Autodesk Fusion 360 part; units mm, degrees
(part 2 of 2)
  circle A756 centre (-67.5, 10.9286) radius 0.5
  circle A757 centre (-64.2073, 10.9286) radius 0.5
  circle A758 centre (-60.9146, 10.9286) radius 0.5
  circle A759 centre (-57.622, 10.9286) radius 0.5
  circle A760 centre (-54.3293, 10.9286) radius 0.5
  circle A761 centre (-51.0366, 10.9286) radius 0.5
  circle A762 centre (-47.7439, 10.9286) radius 0.5
  circle A763 centre (-44.4512, 10.9286) radius 0.5
  circle A764 centre (-41.1585, 10.9286) radius 0.5
  circle A765 centre (-37.8659, 10.9286) radius 0.5
  circle A766 centre (-34.5732, 10.9286) radius 0.5
  circle A767 centre (-31.2805, 10.9286) radius 0.5
  circle A768 centre (-27.9878, 10.9286) radius 0.5
  circle A769 centre (-24.6951, 10.9286) radius 0.5
  circle A770 centre (-21.4024, 10.9286) radius 0.5
  circle A771 centre (-18.1098, 10.9286) radius 0.5
  circle A772 centre (-14.8171, 10.9286) radius 0.5
  circle A773 centre (-11.5244, 10.9286) radius 0.5
  circle A774 centre (-8.2317, 10.9286) radius 0.5
  circle A775 centre (-4.939, 10.9286) radius 0.5
  circle A776 centre (-1.6463, 10.9286) radius 0.5
  circle A777 centre (1.6463, 10.9286) radius 0.5
  circle A778 centre (4.939, 10.9286) radius 0.5
  circle A779 centre (8.2317, 10.9286) radius 0.5
  circle A780 centre (11.5244, 10.9286) radius 0.5
  circle A781 centre (14.8171, 10.9286) radius 0.5
  circle A782 centre (18.1098, 10.9286) radius 0.5
  circle A783 centre (21.4024, 10.9286) radius 0.5
  circle A784 centre (24.6951, 10.9286) radius 0.5
  circle A785 centre (27.9878, 10.9286) radius 0.5
  circle A786 centre (31.2805, 10.9286) radius 0.5
  circle A787 centre (34.5732, 10.9286) radius 0.5
  circle A788 centre (37.8659, 10.9286) radius 0.5
  circle A789 centre (41.1585, 10.9286) radius 0.5
  circle A790 centre (44.4512, 10.9286) radius 0.5
  circle A791 centre (47.7439, 10.9286) radius 0.5
  circle A792 centre (51.0366, 10.9286) radius 0.5
  circle A793 centre (54.3293, 10.9286) radius 0.5
  circle A794 centre (57.622, 10.9286) radius 0.5
  circle A795 centre (60.9146, 10.9286) radius 0.5
  circle A796 centre (64.2073, 10.9286) radius 0.5
  circle A797 centre (67.5, 10.9286) radius 0.5
  circle A798 centre (-67.5, 13.7857) radius 0.5
  circle A799 centre (-64.2073, 13.7857) radius 0.5
  circle A800 centre (-60.9146, 13.7857) radius 0.5
  circle A801 centre (-57.622, 13.7857) radius 0.5
  circle A802 centre (-54.3293, 13.7857) radius 0.5
  circle A803 centre (-51.0366, 13.7857) radius 0.5
  circle A804 centre (-47.7439, 13.7857) radius 0.5
  circle A805 centre (-44.4512, 13.7857) radius 0.5
  circle A806 centre (-41.1585, 13.7857) radius 0.5
  circle A807 centre (-37.8659, 13.7857) radius 0.5
  circle A808 centre (-34.5732, 13.7857) radius 0.5
  circle A809 centre (-31.2805, 13.7857) radius 0.5
  circle A810 centre (-27.9878, 13.7857) radius 0.5
  circle A811 centre (-24.6951, 13.7857) radius 0.5
  circle A812 centre (-21.4024, 13.7857) radius 0.5
  circle A813 centre (-18.1098, 13.7857) radius 0.5
  circle A814 centre (-14.8171, 13.7857) radius 0.5
  circle A815 centre (-11.5244, 13.7857) radius 0.5
  circle A816 centre (-8.2317, 13.7857) radius 0.5
  circle A817 centre (-4.939, 13.7857) radius 0.5
  circle A818 centre (-1.6463, 13.7857) radius 0.5
  circle A819 centre (1.6463, 13.7857) radius 0.5
  circle A820 centre (4.939, 13.7857) radius 0.5
  circle A821 centre (8.2317, 13.7857) radius 0.5
  circle A822 centre (11.5244, 13.7857) radius 0.5
  circle A823 centre (14.8171, 13.7857) radius 0.5
  circle A824 centre (18.1098, 13.7857) radius 0.5
  circle A825 centre (21.4024, 13.7857) radius 0.5
  circle A826 centre (24.6951, 13.7857) radius 0.5
  circle A827 centre (27.9878, 13.7857) radius 0.5
  circle A828 centre (31.2805, 13.7857) radius 0.5
  circle A829 centre (34.5732, 13.7857) radius 0.5
  circle A830 centre (37.8659, 13.7857) radius 0.5
  circle A831 centre (41.1585, 13.7857) radius 0.5
  circle A832 centre (44.4512, 13.7857) radius 0.5
  circle A833 centre (47.7439, 13.7857) radius 0.5
  circle A834 centre (51.0366, 13.7857) radius 0.5
  circle A835 centre (54.3293, 13.7857) radius 0.5
  circle A836 centre (57.622, 13.7857) radius 0.5
  circle A837 centre (60.9146, 13.7857) radius 0.5
  circle A838 centre (64.2073, 13.7857) radius 0.5
  circle A839 centre (67.5, 13.7857) radius 0.5
  circle A840 centre (-67.5, 16.6429) radius 0.5
  circle A841 centre (-64.2073, 16.6429) radius 0.5
  circle A842 centre (-60.9146, 16.6429) radius 0.5
  circle A843 centre (-57.622, 16.6429) radius 0.5
  circle A844 centre (-54.3293, 16.6429) radius 0.5
  circle A845 centre (-51.0366, 16.6429) radius 0.5
  circle A846 centre (-47.7439, 16.6429) radius 0.5
  circle A847 centre (-44.4512, 16.6429) radius 0.5
  circle A848 centre (-41.1585, 16.6429) radius 0.5
  circle A849 centre (-37.8659, 16.6429) radius 0.5
  circle A850 centre (-34.5732, 16.6429) radius 0.5
  circle A851 centre (-31.2805, 16.6429) radius 0.5
  circle A852 centre (-27.9878, 16.6429) radius 0.5
  circle A853 centre (-24.6951, 16.6429) radius 0.5
  circle A854 centre (-21.4024, 16.6429) radius 0.5
  circle A855 centre (-18.1098, 16.6429) radius 0.5
  circle A856 centre (-14.8171, 16.6429) radius 0.5
  circle A857 centre (-11.5244, 16.6429) radius 0.5
  circle A858 centre (-8.2317, 16.6429) radius 0.5
  circle A859 centre (-4.939, 16.6429) radius 0.5
  circle A860 centre (-1.6463, 16.6429) radius 0.5
  circle A861 centre (1.6463, 16.6429) radius 0.5
  circle A862 centre (4.939, 16.6429) radius 0.5
  circle A863 centre (8.2317, 16.6429) radius 0.5
  circle A864 centre (11.5244, 16.6429) radius 0.5
  circle A865 centre (14.8171, 16.6429) radius 0.5
  circle A866 centre (18.1098, 16.6429) radius 0.5
  circle A867 centre (21.4024, 16.6429) radius 0.5
  circle A868 centre (24.6951, 16.6429) radius 0.5
  circle A869 centre (27.9878, 16.6429) radius 0.5
  circle A870 centre (31.2805, 16.6429) radius 0.5
  circle A871 centre (34.5732, 16.6429) radius 0.5
  circle A872 centre (37.8659, 16.6429) radius 0.5
  circle A873 centre (41.1585, 16.6429) radius 0.5
  circle A874 centre (44.4512, 16.6429) radius 0.5
  circle A875 centre (47.7439, 16.6429) radius 0.5
  circle A876 centre (51.0366, 16.6429) radius 0.5
  circle A877 centre (54.3293, 16.6429) radius 0.5
  circle A878 centre (57.622, 16.6429) radius 0.5
  circle A879 centre (60.9146, 16.6429) radius 0.5
  circle A880 centre (64.2073, 16.6429) radius 0.5
  circle A881 centre (67.5, 16.6429) radius 0.5
  circle A882 centre (-67.5, 19.5) radius 0.5
  circle A883 centre (-64.2073, 19.5) radius 0.5
  circle A884 centre (-60.9146, 19.5) radius 0.5
  circle A885 centre (-57.622, 19.5) radius 0.5
  circle A886 centre (-54.3293, 19.5) radius 0.5
  circle A887 centre (-51.0366, 19.5) radius 0.5
  circle A888 centre (-47.7439, 19.5) radius 0.5
  circle A889 centre (-44.4512, 19.5) radius 0.5
  circle A890 centre (-41.1585, 19.5) radius 0.5
  circle A891 centre (-37.8659, 19.5) radius 0.5
  circle A892 centre (-34.5732, 19.5) radius 0.5
  circle A893 centre (-31.2805, 19.5) radius 0.5
  circle A894 centre (-27.9878, 19.5) radius 0.5
  circle A895 centre (-24.6951, 19.5) radius 0.5
  circle A896 centre (-21.4024, 19.5) radius 0.5
  circle A897 centre (-18.1098, 19.5) radius 0.5
  circle A898 centre (-14.8171, 19.5) radius 0.5
  circle A899 centre (-11.5244, 19.5) radius 0.5
  circle A900 centre (-8.2317, 19.5) radius 0.5
  circle A901 centre (-4.939, 19.5) radius 0.5
  circle A902 centre (-1.6463, 19.5) radius 0.5
  circle A903 centre (1.6463, 19.5) radius 0.5
  circle A904 centre (4.939, 19.5) radius 0.5
  circle A905 centre (8.2317, 19.5) radius 0.5
  circle A906 centre (11.5244, 19.5) radius 0.5
  circle A907 centre (14.8171, 19.5) radius 0.5
  circle A908 centre (18.1098, 19.5) radius 0.5
  circle A909 centre (21.4024, 19.5) radius 0.5
  circle A910 centre (24.6951, 19.5) radius 0.5
  circle A911 centre (27.9878, 19.5) radius 0.5
  circle A912 centre (31.2805, 19.5) radius 0.5
  circle A913 centre (34.5732, 19.5) radius 0.5
  circle A914 centre (37.8659, 19.5) radius 0.5
  circle A915 centre (41.1585, 19.5) radius 0.5
  circle A916 centre (44.4512, 19.5) radius 0.5
  circle A917 centre (47.7439, 19.5) radius 0.5
  circle A918 centre (51.0366, 19.5) radius 0.5
  circle A919 centre (54.3293, 19.5) radius 0.5
  circle A920 centre (57.622, 19.5) radius 0.5
  circle A921 centre (60.9146, 19.5) radius 0.5
  circle A922 centre (64.2073, 19.5) radius 0.5
  circle A923 centre (67.5, 19.5) radius 0.5
  circle A924 centre (-67.5, 22.3571) radius 0.5
  circle A925 centre (-64.2073, 22.3571) radius 0.5
  circle A926 centre (-60.9146, 22.3571) radius 0.5
  circle A927 centre (-57.622, 22.3571) radius 0.5
  circle A928 centre (-54.3293, 22.3571) radius 0.5
  circle A929 centre (-51.0366, 22.3571) radius 0.5
  circle A930 centre (-47.7439, 22.3571) radius 0.5
  circle A931 centre (-44.4512, 22.3571) radius 0.5
  circle A932 centre (-41.1585, 22.3571) radius 0.5
  circle A933 centre (-37.8659, 22.3571) radius 0.5
  circle A934 centre (-34.5732, 22.3571) radius 0.5
  circle A935 centre (-31.2805, 22.3571) radius 0.5
  circle A936 centre (-27.9878, 22.3571) radius 0.5
  circle A937 centre (-24.6951, 22.3571) radius 0.5
  circle A938 centre (-21.4024, 22.3571) radius 0.5
  circle A939 centre (-18.1098, 22.3571) radius 0.5
  circle A940 centre (-14.8171, 22.3571) radius 0.5
  circle A941 centre (-11.5244, 22.3571) radius 0.5
  circle A942 centre (-8.2317, 22.3571) radius 0.5
  circle A943 centre (-4.939, 22.3571) radius 0.5
  circle A944 centre (-1.6463, 22.3571) radius 0.5
  circle A945 centre (1.6463, 22.3571) radius 0.5
  circle A946 centre (4.939, 22.3571) radius 0.5
  circle A947 centre (8.2317, 22.3571) radius 0.5
  circle A948 centre (11.5244, 22.3571) radius 0.5
  circle A949 centre (14.8171, 22.3571) radius 0.5
  circle A950 centre (18.1098, 22.3571) radius 0.5
  circle A951 centre (21.4024, 22.3571) radius 0.5
  circle A952 centre (24.6951, 22.3571) radius 0.5
  circle A953 centre (27.9878, 22.3571) radius 0.5
  circle A954 centre (31.2805, 22.3571) radius 0.5
  circle A955 centre (34.5732, 22.3571) radius 0.5
  circle A956 centre (37.8659, 22.3571) radius 0.5
  circle A957 centre (41.1585, 22.3571) radius 0.5
  circle A958 centre (44.4512, 22.3571) radius 0.5
  circle A959 centre (47.7439, 22.3571) radius 0.5
  circle A960 centre (51.0366, 22.3571) radius 0.5
  circle A961 centre (54.3293, 22.3571) radius 0.5
  circle A962 centre (57.622, 22.3571) radius 0.5
  circle A963 centre (60.9146, 22.3571) radius 0.5
  circle A964 centre (64.2073, 22.3571) radius 0.5
  circle A965 centre (67.5, 22.3571) radius 0.5
  circle A966 centre (-67.5, 25.2143) radius 0.5
  circle A967 centre (-64.2073, 25.2143) radius 0.5
  circle A968 centre (-60.9146, 25.2143) radius 0.5
  circle A969 centre (-57.622, 25.2143) radius 0.5
  circle A970 centre (-54.3293, 25.2143) radius 0.5
  circle A971 centre (-51.0366, 25.2143) radius 0.5
  circle A972 centre (-47.7439, 25.2143) radius 0.5
  circle A973 centre (-44.4512, 25.2143) radius 0.5
  circle A974 centre (-41.1585, 25.2143) radius 0.5
  circle A975 centre (-37.8659, 25.2143) radius 0.5
  circle A976 centre (-34.5732, 25.2143) radius 0.5
  circle A977 centre (-31.2805, 25.2143) radius 0.5
  circle A978 centre (-27.9878, 25.2143) radius 0.5
  circle A979 centre (-24.6951, 25.2143) radius 0.5
  circle A980 centre (-21.4024, 25.2143) radius 0.5
  circle A981 centre (-18.1098, 25.2143) radius 0.5
  circle A982 centre (-14.8171, 25.2143) radius 0.5
  circle A983 centre (-11.5244, 25.2143) radius 0.5
  circle A984 centre (-8.2317, 25.2143) radius 0.5
  circle A985 centre (-4.939, 25.2143) radius 0.5
  circle A986 centre (-1.6463, 25.2143) radius 0.5
  circle A987 centre (1.6463, 25.2143) radius 0.5
  circle A988 centre (4.939, 25.2143) radius 0.5
  circle A989 centre (8.2317, 25.2143) radius 0.5
  circle A990 centre (11.5244, 25.2143) radius 0.5
  circle A991 centre (14.8171, 25.2143) radius 0.5
  circle A992 centre (18.1098, 25.2143) radius 0.5
  circle A993 centre (21.4024, 25.2143) radius 0.5
  circle A994 centre (24.6951, 25.2143) radius 0.5
  circle A995 centre (27.9878, 25.2143) radius 0.5
  circle A996 centre (31.2805, 25.2143) radius 0.5
  circle A997 centre (34.5732, 25.2143) radius 0.5
  circle A998 centre (37.8659, 25.2143) radius 0.5
  circle A999 centre (41.1585, 25.2143) radius 0.5
  circle A1000 centre (44.4512, 25.2143) radius 0.5
  circle A1001 centre (47.7439, 25.2143) radius 0.5
  circle A1002 centre (51.0366, 25.2143) radius 0.5
  circle A1003 centre (54.3293, 25.2143) radius 0.5
  circle A1004 centre (57.622, 25.2143) radius 0.5
  circle A1005 centre (60.9146, 25.2143) radius 0.5
  circle A1006 centre (64.2073, 25.2143) radius 0.5
  circle A1007 centre (67.5, 25.2143) radius 0.5
  circle A1008 centre (-67.5, 28.0714) radius 0.5
  circle A1009 centre (-64.2073, 28.0714) radius 0.5
  circle A1010 centre (-60.9146, 28.0714) radius 0.5
  circle A1011 centre (-57.622, 28.0714) radius 0.5
  circle A1012 centre (-54.3293, 28.0714) radius 0.5
  circle A1013 centre (-51.0366, 28.0714) radius 0.5
  circle A1014 centre (-47.7439, 28.0714) radius 0.5
  circle A1015 centre (-44.4512, 28.0714) radius 0.5
  circle A1016 centre (-41.1585, 28.0714) radius 0.5
  circle A1017 centre (-37.8659, 28.0714) radius 0.5
  circle A1018 centre (-34.5732, 28.0714) radius 0.5
  circle A1019 centre (-31.2805, 28.0714) radius 0.5
  circle A1020 centre (-27.9878, 28.0714) radius 0.5
  circle A1021 centre (-24.6951, 28.0714) radius 0.5
  circle A1022 centre (-21.4024, 28.0714) radius 0.5
  circle A1023 centre (-18.1098, 28.0714) radius 0.5
  circle A1024 centre (-14.8171, 28.0714) radius 0.5
  circle A1025 centre (-11.5244, 28.0714) radius 0.5
  circle A1026 centre (-8.2317, 28.0714) radius 0.5
  circle A1027 centre (-4.939, 28.0714) radius 0.5
  circle A1028 centre (-1.6463, 28.0714) radius 0.5
  circle A1029 centre (1.6463, 28.0714) radius 0.5
  circle A1030 centre (4.939, 28.0714) radius 0.5
  circle A1031 centre (8.2317, 28.0714) radius 0.5
  circle A1032 centre (11.5244, 28.0714) radius 0.5
  circle A1033 centre (14.8171, 28.0714) radius 0.5
  circle A1034 centre (18.1098, 28.0714) radius 0.5
  circle A1035 centre (21.4024, 28.0714) radius 0.5
  circle A1036 centre (24.6951, 28.0714) radius 0.5
  circle A1037 centre (27.9878, 28.0714) radius 0.5
  circle A1038 centre (31.2805, 28.0714) radius 0.5
  circle A1039 centre (34.5732, 28.0714) radius 0.5
  circle A1040 centre (37.8659, 28.0714) radius 0.5
  circle A1041 centre (41.1585, 28.0714) radius 0.5
  circle A1042 centre (44.4512, 28.0714) radius 0.5
  circle A1043 centre (47.7439, 28.0714) radius 0.5
  circle A1044 centre (51.0366, 28.0714) radius 0.5
  circle A1045 centre (54.3293, 28.0714) radius 0.5
  circle A1046 centre (57.622, 28.0714) radius 0.5
  circle A1047 centre (60.9146, 28.0714) radius 0.5
  circle A1048 centre (64.2073, 28.0714) radius 0.5
  circle A1049 centre (67.5, 28.0714) radius 0.5
  circle A1050 centre (-67.5, 30.9286) radius 0.5
  circle A1051 centre (-64.2073, 30.9286) radius 0.5
  circle A1052 centre (-60.9146, 30.9286) radius 0.5
  circle A1053 centre (-57.622, 30.9286) radius 0.5
  circle A1054 centre (-54.3293, 30.9286) radius 0.5
  circle A1055 centre (-51.0366, 30.9286) radius 0.5
  circle A1056 centre (-47.7439, 30.9286) radius 0.5
  circle A1057 centre (-44.4512, 30.9286) radius 0.5
  circle A1058 centre (-41.1585, 30.9286) radius 0.5
  circle A1059 centre (-37.8659, 30.9286) radius 0.5
  circle A1060 centre (-34.5732, 30.9286) radius 0.5
  circle A1061 centre (-31.2805, 30.9286) radius 0.5
  circle A1062 centre (-27.9878, 30.9286) radius 0.5
  circle A1063 centre (-24.6951, 30.9286) radius 0.5
  circle A1064 centre (-21.4024, 30.9286) radius 0.5
  circle A1065 centre (-18.1098, 30.9286) radius 0.5
  circle A1066 centre (-14.8171, 30.9286) radius 0.5
  circle A1067 centre (-11.5244, 30.9286) radius 0.5
  circle A1068 centre (-8.2317, 30.9286) radius 0.5
  circle A1069 centre (-4.939, 30.9286) radius 0.5
  circle A1070 centre (-1.6463, 30.9286) radius 0.5
  circle A1071 centre (1.6463, 30.9286) radius 0.5
  circle A1072 centre (4.939, 30.9286) radius 0.5
  circle A1073 centre (8.2317, 30.9286) radius 0.5
  circle A1074 centre (11.5244, 30.9286) radius 0.5
  circle A1075 centre (14.8171, 30.9286) radius 0.5
  circle A1076 centre (18.1098, 30.9286) radius 0.5
  circle A1077 centre (21.4024, 30.9286) radius 0.5
  circle A1078 centre (24.6951, 30.9286) radius 0.5
  circle A1079 centre (27.9878, 30.9286) radius 0.5
  circle A1080 centre (31.2805, 30.9286) radius 0.5
  circle A1081 centre (34.5732, 30.9286) radius 0.5
  circle A1082 centre (37.8659, 30.9286) radius 0.5
  circle A1083 centre (41.1585, 30.9286) radius 0.5
  circle A1084 centre (44.4512, 30.9286) radius 0.5
  circle A1085 centre (47.7439, 30.9286) radius 0.5
  circle A1086 centre (51.0366, 30.9286) radius 0.5
  circle A1087 centre (54.3293, 30.9286) radius 0.5
  circle A1088 centre (57.622, 30.9286) radius 0.5
  circle A1089 centre (60.9146, 30.9286) radius 0.5
  circle A1090 centre (64.2073, 30.9286) radius 0.5
  circle A1091 centre (67.5, 30.9286) radius 0.5
  circle A1092 centre (-67.5, 33.7857) radius 0.5
  circle A1093 centre (-64.2073, 33.7857) radius 0.5
  circle A1094 centre (-60.9146, 33.7857) radius 0.5
  circle A1095 centre (-57.622, 33.7857) radius 0.5
  circle A1096 centre (-54.3293, 33.7857) radius 0.5
  circle A1097 centre (-51.0366, 33.7857) radius 0.5
  circle A1098 centre (-47.7439, 33.7857) radius 0.5
  circle A1099 centre (-44.4512, 33.7857) radius 0.5
  circle A1100 centre (-41.1585, 33.7857) radius 0.5
  circle A1101 centre (-37.8659, 33.7857) radius 0.5
  circle A1102 centre (-34.5732, 33.7857) radius 0.5
  circle A1103 centre (-31.2805, 33.7857) radius 0.5
  circle A1104 centre (-27.9878, 33.7857) radius 0.5
  circle A1105 centre (-24.6951, 33.7857) radius 0.5
  circle A1106 centre (-21.4024, 33.7857) radius 0.5
  circle A1107 centre (-18.1098, 33.7857) radius 0.5
  circle A1108 centre (-14.8171, 33.7857) radius 0.5
  circle A1109 centre (-11.5244, 33.7857) radius 0.5
  circle A1110 centre (-8.2317, 33.7857) radius 0.5
  circle A1111 centre (-4.939, 33.7857) radius 0.5
  circle A1112 centre (-1.6463, 33.7857) radius 0.5
  circle A1113 centre (1.6463, 33.7857) radius 0.5
  circle A1114 centre (4.939, 33.7857) radius 0.5
  circle A1115 centre (8.2317, 33.7857) radius 0.5
  circle A1116 centre (11.5244, 33.7857) radius 0.5
  circle A1117 centre (14.8171, 33.7857) radius 0.5
  circle A1118 centre (18.1098, 33.7857) radius 0.5
  circle A1119 centre (21.4024, 33.7857) radius 0.5
  circle A1120 centre (24.6951, 33.7857) radius 0.5
  circle A1121 centre (27.9878, 33.7857) radius 0.5
  circle A1122 centre (31.2805, 33.7857) radius 0.5
  circle A1123 centre (34.5732, 33.7857) radius 0.5
  circle A1124 centre (37.8659, 33.7857) radius 0.5
  circle A1125 centre (41.1585, 33.7857) radius 0.5
  circle A1126 centre (44.4512, 33.7857) radius 0.5
  circle A1127 centre (47.7439, 33.7857) radius 0.5
  circle A1128 centre (51.0366, 33.7857) radius 0.5
  circle A1129 centre (54.3293, 33.7857) radius 0.5
  circle A1130 centre (57.622, 33.7857) radius 0.5
  circle A1131 centre (60.9146, 33.7857) radius 0.5
  circle A1132 centre (64.2073, 33.7857) radius 0.5
  circle A1133 centre (67.5, 33.7857) radius 0.5
  circle A1134 centre (-67.5, 36.6429) radius 0.5
  circle A1135 centre (-64.2073, 36.6429) radius 0.5
  circle A1136 centre (-60.9146, 36.6429) radius 0.5
  circle A1137 centre (-57.622, 36.6429) radius 0.5
  circle A1138 centre (-54.3293, 36.6429) radius 0.5
  circle A1139 centre (-51.0366, 36.6429) radius 0.5
  circle A1140 centre (-47.7439, 36.6429) radius 0.5
  circle A1141 centre (-44.4512, 36.6429) radius 0.5
  circle A1142 centre (-41.1585, 36.6429) radius 0.5
  circle A1143 centre (-37.8659, 36.6429) radius 0.5
  circle A1144 centre (-34.5732, 36.6429) radius 0.5
  circle A1145 centre (-31.2805, 36.6429) radius 0.5
  circle A1146 centre (-27.9878, 36.6429) radius 0.5
  circle A1147 centre (-24.6951, 36.6429) radius 0.5
  circle A1148 centre (-21.4024, 36.6429) radius 0.5
  circle A1149 centre (-18.1098, 36.6429) radius 0.5
  circle A1150 centre (-14.8171, 36.6429) radius 0.5
  circle A1151 centre (-11.5244, 36.6429) radius 0.5
  circle A1152 centre (-8.2317, 36.6429) radius 0.5
  circle A1153 centre (-4.939, 36.6429) radius 0.5
  circle A1154 centre (-1.6463, 36.6429) radius 0.5
  circle A1155 centre (1.6463, 36.6429) radius 0.5
  circle A1156 centre (4.939, 36.6429) radius 0.5
  circle A1157 centre (8.2317, 36.6429) radius 0.5
  circle A1158 centre (11.5244, 36.6429) radius 0.5
  circle A1159 centre (14.8171, 36.6429) radius 0.5
  circle A1160 centre (18.1098, 36.6429) radius 0.5
  circle A1161 centre (21.4024, 36.6429) radius 0.5
  circle A1162 centre (24.6951, 36.6429) radius 0.5
  circle A1163 centre (27.9878, 36.6429) radius 0.5
  circle A1164 centre (31.2805, 36.6429) radius 0.5
  circle A1165 centre (34.5732, 36.6429) radius 0.5
  circle A1166 centre (37.8659, 36.6429) radius 0.5
  circle A1167 centre (41.1585, 36.6429) radius 0.5
  circle A1168 centre (44.4512, 36.6429) radius 0.5
  circle A1169 centre (47.7439, 36.6429) radius 0.5
  circle A1170 centre (51.0366, 36.6429) radius 0.5
  circle A1171 centre (54.3293, 36.6429) radius 0.5
  circle A1172 centre (57.622, 36.6429) radius 0.5
  circle A1173 centre (60.9146, 36.6429) radius 0.5
  circle A1174 centre (64.2073, 36.6429) radius 0.5
  circle A1175 centre (67.5, 36.6429) radius 0.5
  circle A1176 centre (-67.5, 39.5) radius 0.5
  circle A1177 centre (-64.2073, 39.5) radius 0.5
  circle A1178 centre (-60.9146, 39.5) radius 0.5
  circle A1179 centre (-57.622, 39.5) radius 0.5
  circle A1180 centre (-54.3293, 39.5) radius 0.5
  circle A1181 centre (-51.0366, 39.5) radius 0.5
  circle A1182 centre (-47.7439, 39.5) radius 0.5
  circle A1183 centre (-44.4512, 39.5) radius 0.5
  circle A1184 centre (-41.1585, 39.5) radius 0.5
  circle A1185 centre (-37.8659, 39.5) radius 0.5
  circle A1186 centre (-34.5732, 39.5) radius 0.5
  circle A1187 centre (-31.2805, 39.5) radius 0.5
  circle A1188 centre (-27.9878, 39.5) radius 0.5
  circle A1189 centre (-24.6951, 39.5) radius 0.5
  circle A1190 centre (-21.4024, 39.5) radius 0.5
  circle A1191 centre (-18.1098, 39.5) radius 0.5
  circle A1192 centre (-14.8171, 39.5) radius 0.5
  circle A1193 centre (-11.5244, 39.5) radius 0.5
  circle A1194 centre (-8.2317, 39.5) radius 0.5
  circle A1195 centre (-4.939, 39.5) radius 0.5
  circle A1196 centre (-1.6463, 39.5) radius 0.5
  circle A1197 centre (1.6463, 39.5) radius 0.5
  circle A1198 centre (4.939, 39.5) radius 0.5
  circle A1199 centre (8.2317, 39.5) radius 0.5
  circle A1200 centre (11.5244, 39.5) radius 0.5
  circle A1201 centre (14.8171, 39.5) radius 0.5
  circle A1202 centre (18.1098, 39.5) radius 0.5
  circle A1203 centre (21.4024, 39.5) radius 0.5
  circle A1204 centre (24.6951, 39.5) radius 0.5
  circle A1205 centre (27.9878, 39.5) radius 0.5
  circle A1206 centre (31.2805, 39.5) radius 0.5
  circle A1207 centre (34.5732, 39.5) radius 0.5
  circle A1208 centre (37.8659, 39.5) radius 0.5
  circle A1209 centre (41.1585, 39.5) radius 0.5
  circle A1210 centre (44.4512, 39.5) radius 0.5
  circle A1211 centre (47.7439, 39.5) radius 0.5
  circle A1212 centre (51.0366, 39.5) radius 0.5
  circle A1213 centre (54.3293, 39.5) radius 0.5
  circle A1214 centre (57.622, 39.5) radius 0.5
  circle A1215 centre (60.9146, 39.5) radius 0.5
  circle A1216 centre (64.2073, 39.5) radius 0.5
  circle A1217 centre (67.5, 39.5) radius 0.5
  dimension "d5" = 82
  dimension "d6" = 136
  dimension "d9" = 135
  dimension "d10" = 80
  constraint vertical L0
  constraint perpendicular L0 L1
  constraint perpendicular L1 L2
  constraint perpendicular L0 L3
  constraint symmetric L0 L2 L4
  constraint symmetric L1 L3 L5
  constraint tangent L0 A0
  measures "d5" distance of L0.start L0.end
  measures "d6" distance of L0.end L1.end
extrude "拉伸2" add sketch "草图2" along normal blind 1 separate body contours L0 L3 L4 L5 | L2 L3 L4 L5 | L1 L2 L4 L5 A41 A629 | L0 L1 L4 L5 A0 A588 makes body 2

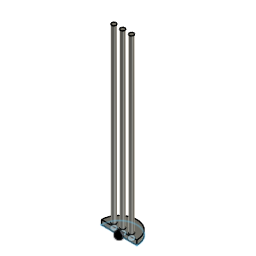
design "LM35DZ v1"
Autodesk Fusion 360 part; units mm, degrees
sketch "草图1" plane through (0, 0, 0) normal (0, 0, 1) x (1, 0, 0)
  line L0 (-2, 0) -> (2, 0)
  arc A0 (2, 0) -> (-2, 0) centre (0, 0) ccw
  circle A1 centre (0, 0.4) radius 0.25
  circle A2 centre (-1, 0.4) radius 0.25
  circle A3 centre (1, 0.4) radius 0.25
  dimension "d2" = 0.5
  dimension "d5" = 1
  dimension "d6" = 0
  constraint coincident A0.centre origin
  constraint horizontal L0
  measures "d2" diameter of A1
extrude "拉伸1" add sketch "草图1" along normal blind 0.5
extrude "拉伸2" add sketch "草图1" along normal blind 20 contours A2
extrude "拉伸3" add sketch "草图1" along normal blind 20 contours A1
extrude "拉伸4" add sketch "草图1" along normal blind 20 contours A3

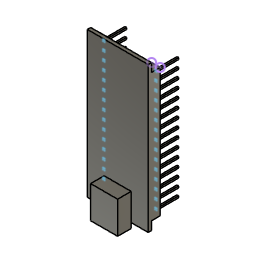
design "nano v1"
Autodesk Fusion 360 part; units mm, degrees
sketch "草图1" plane through (0, 0, 0) normal (0, 1, 0) x (1, 0, 0)
  line L0 (0, 0) -> (18, 0)
  line L1 (18, 0) -> (18, -43)
  line L2 (18, -43) -> (0, -43)
  line L3 (0, -43) -> (0, 0)
  dimension "d1" = 18
  dimension "d2" = 43
  constraint coincident L0.start L3.end
  constraint horizontal L0
  constraint perpendicular L0 L1
  constraint perpendicular L1 L2
  constraint perpendicular L0 L3
  measures "d1" distance of L0.start L0.end
  measures "d2" distance of L0.end L1.end
extrude "拉伸1" add sketch "草图1" along normal blind 1
sketch "草图2" plane through (0, 0, 0) normal (0, -1, 0) x (1, 0, 0)
  line L0 (18, 43) -> (0, 43)
  line L1 (0, 43) -> (0, 0)
  line L2 (0, 0) -> (18, 0)
  line L3 (18, 0) -> (18, 43)
  line L4 (4.9545, 0) -> (12.9545, 0)
  line L5 (12.9545, 0) -> (12.9545, 8)
  line L6 (4.9545, 8) -> (4.9545, 0)
  line L7 (4.9545, 0) -> (4.9545, -1.5)
  line L8 (4.9545, -1.5) -> (12.9545, -1.5)
  line L9 (12.9545, -1.5) -> (12.9545, 0)
  line L10 (12.9545, 8) -> (4.9545, 8)
  dimension "d6" = 8
  dimension "d9" = 1.5
  dimension "d10" = 8
  constraint coincident L2 L4.start
  constraint parallel L2 L4
  constraint perpendicular L4 L5
  constraint perpendicular L4 L7
  constraint perpendicular L7 L8
  measures "d6" distance of L4.start L4.end
  measures "d9" distance of L4.start L7.end
  measures "d10" distance of L7.end L8.end
extrude "拉伸2" add sketch "草图2" along normal blind 4 contours L2 L4 L7 L8 L9 | L2 L4 L5 L6 L10
sketch "草图3" plane through (0, 1, 0) normal (0, 1, 0) x (-1, 0, 0)
  line L0 (0, 43) -> (-18, 43)
  line L1 (-18, 43) -> (-18, 0)
  line L2 (-18, 0) -> (0, 0)
  line L3 (0, 0) -> (0, 43)
  line L4 (-18, 21.5) -> (-18, 40)
  line L5 (-18, 40) -> (-15.46, 40)
  line L6 (-15.46, 40) -> (-15.46, 3)
  line L7 (-15.46, 3) -> (-18, 3)
  line L8 (-18, 3) -> (-18, 21.5)
  line L9 (-9, 43) -> (-9, 0)
  line L10 (0, 21.5) -> (0, 40)
  line L11 (0, 3) -> (0, 21.5)
  line L12 (-2.54, 40) -> (-2.54, 3)
  line L13 (0, 40) -> (-2.54, 40)
  line L14 (-2.54, 3) -> (0, 3)
  dimension "d14" = 18.5
  dimension "d15" = 2.54
  dimension "d16" = 37
  constraint midpoint L1 L4.start
  constraint parallel L1 L4
  constraint perpendicular L4 L5
  constraint perpendicular L5 L6
  constraint coincident L1 L7.end
  constraint perpendicular L1 L7
  constraint midpoint L0 L9.start
  constraint midpoint L2 L9.end
  constraint symmetric L4.start L9 L10.start
  constraint symmetric L4.end L9 L10.end
  constraint symmetric L5.end L9 L12.start
  constraint symmetric L6.end L9 L12.end
  constraint symmetric L7.end L9 L11.start
  measures "d14" distance of L4.start L4.end
  measures "d15" distance of L4.end L5.end
  measures "d16" distance of L5.end L6.end
extrude "拉伸3" add sketch "草图3" along normal blind 2.54 contours L1 L4 L5 L6 L7 L8
extrude "拉伸4" add sketch "草图3" along normal blind 2.54 contours L3 L10 L11 L12 L13 L14
sketch "草图4" plane through (0, 3.54, 0) normal (0, 1, 0) x (-1, 0, 0)
  line L0 (-18, 3) -> (-15.46, 3)
  line L1 (-15.46, 3) -> (-15.46, 40)
  line L2 (-15.46, 40) -> (-18, 40)
  line L3 (-18, 40) -> (-18, 3)
extrude "拉伸5" add 1 faces at (17.1533, 2.6933, 3) along direction (0, 0, -1) blind 0.5
extrude "拉伸6" add 1 faces at (16.3067, 2.6933, 40) along direction (0, 0, 1) blind 0.5
extrude "拉伸7" add 1 faces at (0.8467, 1.8467, 40) along direction (0, 0, 1) blind 0.5
extrude "拉伸8" add 1 faces at (1.6933, 1.8467, 3) along direction (0, 0, -1) blind 0.5
sketch "草图6" plane through (0, 3.54, 0) normal (0, 1, 0) x (-1, 0, 0)
  line L0 (-18, 40.5) -> (-15.46, 40.5)
  line L1 (-16.73, 39.27) -> (-16.48, 39.27)
  line L2 (-16.48, 39.27) -> (-16.48, 38.77)
  line L3 (-16.48, 38.77) -> (-16.98, 38.77)
  line L4 (-16.98, 38.77) -> (-16.98, 39.27)
  line L5 (-16.98, 39.27) -> (-16.73, 39.27)
  line L6 (-1.08, 39.27) -> (-1.08, 38.77)
  line L7 (-1.33, 39.27) -> (-1.08, 39.27)
  line L8 (-1.58, 39.27) -> (-1.33, 39.27)
  line L9 (-1.58, 38.77) -> (-1.58, 39.27)
  line L10 (-1.08, 38.77) -> (-1.58, 38.77)
  line L11 (-16.48, 36.7414) -> (-16.48, 36.2414)
  line L12 (-16.73, 36.7414) -> (-16.48, 36.7414)
  line L13 (-16.98, 36.7414) -> (-16.73, 36.7414)
  line L14 (-16.98, 36.2414) -> (-16.98, 36.7414)
  line L15 (-16.48, 36.2414) -> (-16.98, 36.2414)
  line L16 (-1.08, 36.7414) -> (-1.08, 36.2414)
  line L17 (-1.33, 36.7414) -> (-1.08, 36.7414)
  line L18 (-1.58, 36.7414) -> (-1.33, 36.7414)
  line L19 (-1.58, 36.2414) -> (-1.58, 36.7414)
  line L20 (-1.08, 36.2414) -> (-1.58, 36.2414)
  line L21 (-16.48, 34.2129) -> (-16.48, 33.7129)
  line L22 (-16.73, 34.2129) -> (-16.48, 34.2129)
  line L23 (-16.98, 34.2129) -> (-16.73, 34.2129)
  line L24 (-16.98, 33.7129) -> (-16.98, 34.2129)
  line L25 (-16.48, 33.7129) -> (-16.98, 33.7129)
  line L26 (-1.08, 34.2129) -> (-1.08, 33.7129)
  line L27 (-1.33, 34.2129) -> (-1.08, 34.2129)
  line L28 (-1.58, 34.2129) -> (-1.33, 34.2129)
  line L29 (-1.58, 33.7129) -> (-1.58, 34.2129)
  line L30 (-1.08, 33.7129) -> (-1.58, 33.7129)
  line L31 (-16.48, 31.6843) -> (-16.48, 31.1843)
  line L32 (-16.73, 31.6843) -> (-16.48, 31.6843)
  line L33 (-16.98, 31.6843) -> (-16.73, 31.6843)
  line L34 (-16.98, 31.1843) -> (-16.98, 31.6843)
  line L35 (-16.48, 31.1843) -> (-16.98, 31.1843)
  line L36 (-1.08, 31.6843) -> (-1.08, 31.1843)
  line L37 (-1.33, 31.6843) -> (-1.08, 31.6843)
  line L38 (-1.58, 31.6843) -> (-1.33, 31.6843)
  line L39 (-1.58, 31.1843) -> (-1.58, 31.6843)
  line L40 (-1.08, 31.1843) -> (-1.58, 31.1843)
  line L41 (-16.48, 29.1557) -> (-16.48, 28.6557)
  line L42 (-16.73, 29.1557) -> (-16.48, 29.1557)
  line L43 (-16.98, 29.1557) -> (-16.73, 29.1557)
  line L44 (-16.98, 28.6557) -> (-16.98, 29.1557)
  line L45 (-16.48, 28.6557) -> (-16.98, 28.6557)
  line L46 (-1.08, 29.1557) -> (-1.08, 28.6557)
  line L47 (-1.33, 29.1557) -> (-1.08, 29.1557)
  line L48 (-1.58, 29.1557) -> (-1.33, 29.1557)
  line L49 (-1.58, 28.6557) -> (-1.58, 29.1557)
  line L50 (-1.08, 28.6557) -> (-1.58, 28.6557)
  line L51 (-16.48, 26.6271) -> (-16.48, 26.1271)
  line L52 (-16.73, 26.6271) -> (-16.48, 26.6271)
  line L53 (-16.98, 26.6271) -> (-16.73, 26.6271)
  line L54 (-16.98, 26.1271) -> (-16.98, 26.6271)
  line L55 (-16.48, 26.1271) -> (-16.98, 26.1271)
  line L56 (-1.08, 26.6271) -> (-1.08, 26.1271)
  line L57 (-1.33, 26.6271) -> (-1.08, 26.6271)
  line L58 (-1.58, 26.6271) -> (-1.33, 26.6271)
  line L59 (-1.58, 26.1271) -> (-1.58, 26.6271)
  line L60 (-1.08, 26.1271) -> (-1.58, 26.1271)
  line L61 (-16.48, 24.0986) -> (-16.48, 23.5986)
  line L62 (-16.73, 24.0986) -> (-16.48, 24.0986)
  line L63 (-16.98, 24.0986) -> (-16.73, 24.0986)
  line L64 (-16.98, 23.5986) -> (-16.98, 24.0986)
  line L65 (-16.48, 23.5986) -> (-16.98, 23.5986)
  line L66 (-1.08, 24.0986) -> (-1.08, 23.5986)
  line L67 (-1.33, 24.0986) -> (-1.08, 24.0986)
  line L68 (-1.58, 24.0986) -> (-1.33, 24.0986)
  line L69 (-1.58, 23.5986) -> (-1.58, 24.0986)
  line L70 (-1.08, 23.5986) -> (-1.58, 23.5986)
  line L71 (-16.48, 21.57) -> (-16.48, 21.07)
  line L72 (-16.73, 21.57) -> (-16.48, 21.57)
  line L73 (-16.98, 21.57) -> (-16.73, 21.57)
  line L74 (-16.98, 21.07) -> (-16.98, 21.57)
  line L75 (-16.48, 21.07) -> (-16.98, 21.07)
  line L76 (-1.08, 21.57) -> (-1.08, 21.07)
  line L77 (-1.33, 21.57) -> (-1.08, 21.57)
  line L78 (-1.58, 21.57) -> (-1.33, 21.57)
  line L79 (-1.58, 21.07) -> (-1.58, 21.57)
  line L80 (-1.08, 21.07) -> (-1.58, 21.07)
  line L81 (-16.48, 19.0414) -> (-16.48, 18.5414)
  line L82 (-16.73, 19.0414) -> (-16.48, 19.0414)
  line L83 (-16.98, 19.0414) -> (-16.73, 19.0414)
  line L84 (-16.98, 18.5414) -> (-16.98, 19.0414)
  line L85 (-16.48, 18.5414) -> (-16.98, 18.5414)
  line L86 (-1.08, 19.0414) -> (-1.08, 18.5414)
  line L87 (-1.33, 19.0414) -> (-1.08, 19.0414)
  line L88 (-1.58, 19.0414) -> (-1.33, 19.0414)
  line L89 (-1.58, 18.5414) -> (-1.58, 19.0414)
  line L90 (-1.08, 18.5414) -> (-1.58, 18.5414)
  line L91 (-16.48, 16.5129) -> (-16.48, 16.0129)
  line L92 (-16.73, 16.5129) -> (-16.48, 16.5129)
  line L93 (-16.98, 16.5129) -> (-16.73, 16.5129)
  line L94 (-16.98, 16.0129) -> (-16.98, 16.5129)
  line L95 (-16.48, 16.0129) -> (-16.98, 16.0129)
  line L96 (-1.08, 16.5129) -> (-1.08, 16.0129)
  line L97 (-1.33, 16.5129) -> (-1.08, 16.5129)
  line L98 (-1.58, 16.5129) -> (-1.33, 16.5129)
  line L99 (-1.58, 16.0129) -> (-1.58, 16.5129)
  line L100 (-1.08, 16.0129) -> (-1.58, 16.0129)
  line L101 (-16.48, 13.9843) -> (-16.48, 13.4843)
  line L102 (-16.73, 13.9843) -> (-16.48, 13.9843)
  line L103 (-16.98, 13.9843) -> (-16.73, 13.9843)
  line L104 (-16.98, 13.4843) -> (-16.98, 13.9843)
  line L105 (-16.48, 13.4843) -> (-16.98, 13.4843)
  line L106 (-1.08, 13.9843) -> (-1.08, 13.4843)
  line L107 (-1.33, 13.9843) -> (-1.08, 13.9843)
  line L108 (-1.58, 13.9843) -> (-1.33, 13.9843)
  line L109 (-1.58, 13.4843) -> (-1.58, 13.9843)
  line L110 (-1.08, 13.4843) -> (-1.58, 13.4843)
  line L111 (-16.48, 11.4557) -> (-16.48, 10.9557)
  line L112 (-16.73, 11.4557) -> (-16.48, 11.4557)
  line L113 (-16.98, 11.4557) -> (-16.73, 11.4557)
  line L114 (-16.98, 10.9557) -> (-16.98, 11.4557)
  line L115 (-16.48, 10.9557) -> (-16.98, 10.9557)
  line L116 (-1.08, 11.4557) -> (-1.08, 10.9557)
  line L117 (-1.33, 11.4557) -> (-1.08, 11.4557)
  line L118 (-1.58, 11.4557) -> (-1.33, 11.4557)
  line L119 (-1.58, 10.9557) -> (-1.58, 11.4557)
  line L120 (-1.08, 10.9557) -> (-1.58, 10.9557)
  line L121 (-16.48, 8.9271) -> (-16.48, 8.4271)
  line L122 (-16.73, 8.9271) -> (-16.48, 8.9271)
  line L123 (-16.98, 8.9271) -> (-16.73, 8.9271)
  line L124 (-16.98, 8.4271) -> (-16.98, 8.9271)
  line L125 (-16.48, 8.4271) -> (-16.98, 8.4271)
  line L126 (-1.08, 8.9271) -> (-1.08, 8.4271)
  line L127 (-1.33, 8.9271) -> (-1.08, 8.9271)
  line L128 (-1.58, 8.9271) -> (-1.33, 8.9271)
  line L129 (-1.58, 8.4271) -> (-1.58, 8.9271)
  line L130 (-1.08, 8.4271) -> (-1.58, 8.4271)
  line L131 (-16.48, 6.3986) -> (-16.48, 5.8986)
  line L132 (-16.73, 6.3986) -> (-16.48, 6.3986)
  line L133 (-16.98, 6.3986) -> (-16.73, 6.3986)
  line L134 (-16.98, 5.8986) -> (-16.98, 6.3986)
  line L135 (-16.48, 5.8986) -> (-16.98, 5.8986)
  line L136 (-1.08, 6.3986) -> (-1.08, 5.8986)
  line L137 (-1.33, 6.3986) -> (-1.08, 6.3986)
  line L138 (-1.58, 6.3986) -> (-1.33, 6.3986)
  line L139 (-1.58, 5.8986) -> (-1.58, 6.3986)
  line L140 (-1.08, 5.8986) -> (-1.58, 5.8986)
  line L141 (-16.48, 3.87) -> (-16.48, 3.37)
  line L142 (-16.73, 3.87) -> (-16.48, 3.87)
  line L143 (-16.98, 3.87) -> (-16.73, 3.87)
  line L144 (-16.98, 3.37) -> (-16.98, 3.87)
  line L145 (-16.48, 3.37) -> (-16.98, 3.37)
  line L146 (-1.08, 3.87) -> (-1.08, 3.37)
  line L147 (-1.33, 3.87) -> (-1.08, 3.87)
  line L148 (-1.58, 3.87) -> (-1.33, 3.87)
  line L149 (-1.58, 3.37) -> (-1.58, 3.87)
  line L150 (-1.08, 3.37) -> (-1.58, 3.37)
  dimension "d35" = 0.25
  dimension "d36" = 0.5
  dimension "d37" = 0.5
  dimension "d38" = 0.5
  dimension "d43" = 15.4
  dimension "d44" = -35.4
  constraint perpendicular L1 L2
  constraint perpendicular L2 L3
  constraint perpendicular L3 L4
  measures "d35" distance of L1.start L1.end
  measures "d36" distance of L1.end L2.end
  measures "d37" distance of L2.end L3.end
  measures "d38" distance of L3.end L4.end
extrude "拉伸9" add sketch "草图6" along normal blind 6.5 contours L1 L2 L3 L4 L5
extrude "拉伸10" add sketch "草图6" along normal blind 6.5 contours L11 L12 L13 L14 L15 | L21 L22 L23 L24 L25 | L31 L32 L33 L34 L35 | L41 L42 L43 L44 L45 | L51 L52 L53 L54 L55 | L61 L62 L63 L64 L65 | L71 L72 L73 L74 L75 | L81 L82 L83 L84 L85 | L91 L92 L93 L94 L95 | L101 L102 L103 L104 L105 | L111 L112 L113 L114 L115 | L121 L122 L123 L124 L125 | L131 L132 L133 L134 L135 | L141 L142 L143 L144 L145
extrude "拉伸11" add sketch "草图6" along normal blind 6.5 contours L6 L7 L8 L9 L10 | L16 L17 L18 L19 L20 | L26 L27 L28 L29 L30 | L36 L37 L38 L39 L40 | L46 L47 L48 L49 L50 | L56 L57 L58 L59 L60 | L66 L67 L68 L69 L70 | L76 L77 L78 L79 L80 | L86 L87 L88 L89 L90 | L96 L97 L98 L99 L100 | L106 L107 L108 L109 L110 | L116 L117 L118 L119 L120 | L126 L127 L128 L129 L130 | L136 L137 L138 L139 L140 | L146 L147 L148 L149 L150
